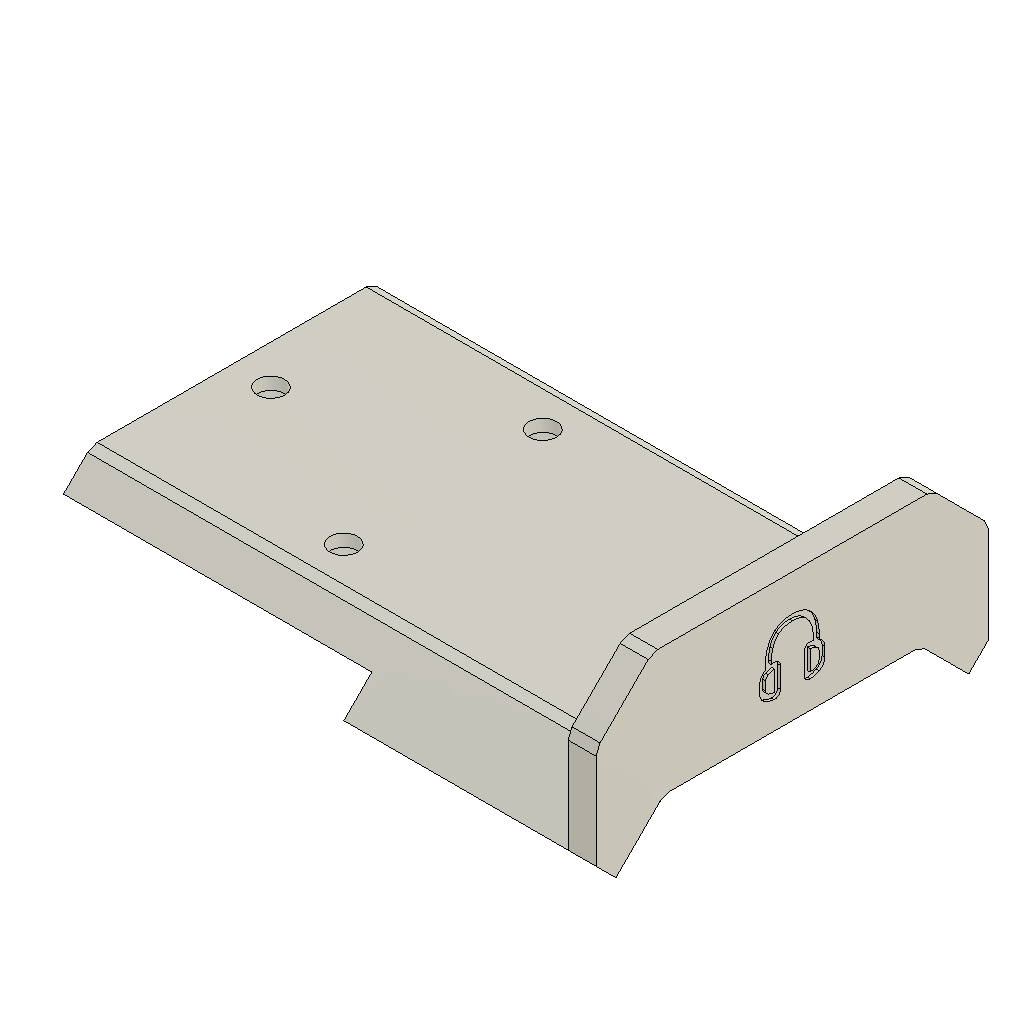
desk (Autodesk Fusion 360 archive; units mm, degrees)
design "headphone holder"
Autodesk Fusion 360 part; units mm, degrees
sketch "Sketch1" plane through (0, 0, 0) normal (1, 0, 0) x (0, 1, 0)
  line L0 (-35, 0) -> (35, 0)
  line L1 (-35, 0) -> (-25, 10)
  line L2 (-25, 10) -> (25, 10)
  line L3 (25, 10) -> (35, 0)
  line L4 (-31.4645, -3.5355) -> (-22.9289, 5)
  line L5 (-22.9289, 5) -> (22.9289, 5)
  line L6 (22.9289, 5) -> (31.4645, -3.5355)
  line L7 (31.4645, -3.5355) -> (35, 0)
  line L8 (-31.4645, -3.5355) -> (-35, 0)
  dimension "d1" = 70
  dimension "d2" = 5
  constraint horizontal L0
  constraint parallel L0 L2
  constraint perpendicular L3 L7
  constraint perpendicular L1 L8
  measures "d1" distance of L0.start L0.end
extrude "Extrude1" add sketch "Sketch1" against normal blind 40 contours L0 L1 L2 L3 L4 L5 L6 | L0 L4 L8 | L0 L6 L7 makes body 1
chamfer "Chamfer1" distance 1 angle 45 4 edges at (-20, 25, 10) (-20, -25, 10) (-20, 22.9289, 5) (-20, -22.9289, 5) tangent chain off on bodies 1
sketch "Sketch2" plane through (0, 0, 0) normal (0, 0, 1) x (1, 0, 0)
  line L0 (0, -35) -> (5, -35)
  line L1 (5, -35) -> (5, 35)
  line L2 (5, 35) -> (0, 35)
  line L3 (0, 35) -> (0, -35)
  constraint horizontal L0
  constraint vertical L1
  constraint horizontal L2
  constraint vertical L3
extrude "Extrude2" add sketch "Sketch2" along normal blind 28 and the other way blind 6 bodies 1
extrude "Extrude3" cut 1 faces at (0, 7.3096, -0.6904) along direction (1, 0, 0) blind 37 on bodies 1 bodies 1
sketch "Sketch3" plane through (0, 0, 0) normal (-1, 0, 0) x (0, -1, 0)
  line L0 (-35, 0) -> (-25.7071, 9.2929)
  line L1 (-25.7071, 9.2929) -> (-24, 10)
  line L2 (-24, 10) -> (24, 10)
  line L3 (24, 10) -> (25.7071, 9.2929)
  line L4 (25.7071, 9.2929) -> (35, 0)
  line L5 (35, 0) -> (35, 28)
  line L6 (35, 28) -> (-35, 28)
  line L7 (-35, 28) -> (-35, 0)
  line L8 (-22.9289, 23) -> (22.9289, 23)
  line L9 (22.9289, 23) -> (31.4645, 14.4645)
  line L10 (-31.4645, 14.4645) -> (-22.9289, 23)
  line L11 (25, 28) -> (35, 18)
  line L12 (31.4645, 14.4645) -> (35, 18)
  line L13 (-31.4645, 14.4645) -> (-35, 18)
  line L14 (-35, 18) -> (-25, 28)
  line L15 (-35, 18) -> (35, 18)
  line L16 (-25, 28) -> (25, 28)
  point P0 (0, 18)
  dimension "d12" = 5
  dimension "d13" = 70
  constraint horizontal L15
  constraint parallel L15 L16
  constraint perpendicular L11 L12
  constraint perpendicular L13 L14
  measures "d13" distance of L11.end L13.end
extrude "Extrude4" cut sketch "Sketch3" against normal blind 10 contours L6 L7 L14 | L5 L6 L11 bodies 1
chamfer "Chamfer2" distance 1 angle 45 4 edges at (2.5, -25, 28) (2.5, 25, 28) (2.5, -35, 18) (2.5, 35, 18) tangent chain off on bodies 1
sketch "Sketch4" plane through (0, 0, 10) normal (0, 0, 1) x (-1, 0, 0)
  line L0 (40, 24) -> (0, 24)
  line L1 (0, 24) -> (0, -24)
  line L2 (0, -24) -> (40, -24)
  line L3 (40, -24) -> (40, 24)
  line L4 (40, 35) -> (95, 35)
  line L5 (95, 35) -> (95, -35)
  line L6 (95, -35) -> (40, -35)
  line L7 (40, -35) -> (40, 35)
  constraint horizontal L4
  constraint vertical L5
  constraint horizontal L6
  constraint vertical L7
extrude "Extrude5" add sketch "Sketch4" against normal blind 4 contours L3 L4 L5 L6 L7 bodies 1
extrude "Extrude6" cut 2 faces at (-40, -29.9024, 8.431) (-40, 29.9024, 8.431) along direction (-1, 0, 0) blind 90 on bodies 1 bodies 1
move_face "OffsetFaces1" offset 1 1 faces at (-76.6667, 8, 6) on bodies 1
sketch "Sketch5" plane through (0, 0, 10) normal (0, 0, 1) x (-1, 0, 0)
  line L0 (95, 24) -> (0, 24)
  line L1 (0, 24) -> (0, -24)
  line L2 (0, -24) -> (95, -24)
  line L3 (95, -24) -> (95, 24)
  circle A0 centre (88, 0) radius 2.45
  line L4 (95, -29.3) -> (40, -29.3)
  line L5 (40, -29.3) -> (40, 29.3)
  line L6 (40, 29.3) -> (95, 29.3)
  line L7 (95, 29.3) -> (95, -29.3)
  circle A1 centre (57.25, 17.7535) radius 2.45
  circle A2 centre (57.25, -17.7535) radius 2.45
  circle A3 centre (67.5, 0) radius 1.5
  point P0 (67.5, 0)
  dimension "d23" = 4.9
  dimension "d25" = 360
  constraint horizontal L4
  constraint vertical L5
  constraint horizontal L6
  constraint vertical L7
  constraint coincident P0 A3.centre
  measures "d23" diameter of A0
extrude "Extrude7" cut sketch "Sketch5" against normal blind 8 contours A0 | A1 | A2 bodies 1
sketch "Sketch6" plane through (0, 0, 5) normal (0, 0, -1) x (1, 0, 0)
  circle A0 centre (-88, 0) radius 2.45
  circle A1 centre (-57.25, 17.7535) radius 2.45
  circle A2 centre (-57.25, -17.7535) radius 2.45
  line L0 (-95, 30) -> (-95, -30)
  line L1 (-40, 21.9289) -> (-40, 30)
  line L2 (-40, -21.9289) -> (5, -21.9289)
  line L3 (5, -21.9289) -> (5, 21.9289)
  line L4 (5, 21.9289) -> (-40, 21.9289)
  circle A3 centre (-57.25, -17.7535) radius 4.5
  circle A4 centre (-88, 0) radius 4.5
  circle A5 centre (-57.25, 17.7535) radius 4.5
  circle A6 centre (-57.25, -17.7535) radius 2.45
  circle A7 centre (-88, 0) radius 2.45
  circle A8 centre (-57.25, 17.7535) radius 2.45
  circle A9 through (-54.8, -17.7535, -2.8) (-58.475, -15.6318, -2.8) (-58.475, -19.8753, -2.8)
  circle A10 through (-85.55, 0, -2.8) (-89.225, 2.1218, -2.8) (-89.225, -2.1218, -2.8)
  circle A11 through (-54.8, 17.7535, -2.8) (-58.475, 19.8753, -2.8) (-58.475, 15.6318, -2.8)
  line L5 (-40, 30) -> (-95, 30)
  line L6 (-95, -30) -> (-40, -30)
  line L7 (-40, -30) -> (-40, -21.9289)
  dimension "d28" = 9
  dimension "d29" = 9
  dimension "d30" = 9
  constraint concentric A2 A3
  constraint concentric A0 A4
  constraint concentric A1 A5
  constraint concentric A3 A6
  constraint concentric A4 A7
  constraint concentric A5 A8
  measures "d28" diameter of A3
  measures "d29" diameter of A4
  measures "d30" diameter of A5
loft "Loft1" add profiles "Sketch6", "Sketch6" section 1 contours A2 A6 | A3 section 2 contours A9 in plane through (0, 0, 7.8) normal (0, 0, -1) separate body makes body 2
extrude "Extrude8" add sketch "Sketch5" along normal blind 2 separate body contours A3 makes body 3
pattern_circular "C-Pattern1" count 3 over 360 about axis through (-67.5, 0, 12) along (0, 0, 1) of bodies 2 makes body 4 at (-87.1, -3.943, 5.6222) makes body 5 at (-53.2507, -17.1507, 5.6222)
delete_body "RemoveBody1" bodies 3
combine "Combine1" operation cut target body 1 tool bodies 5 2 4
sketch "Sketch8" plane through (5, 0, 0) normal (1, 0, 0) x (0, 1, 0)
  line L0 (35, 17) -> (34.2929, 18.7071)
  line L1 (34.2929, 18.7071) -> (25.7071, 27.2929)
  line L2 (25.7071, 27.2929) -> (24, 28)
  line L3 (24, 28) -> (-24, 28)
  line L4 (-24, 28) -> (-25.7071, 27.2929)
  line L5 (-25.7071, 27.2929) -> (-34.2929, 18.7071)
  line L6 (-34.2929, 18.7071) -> (-35, 17)
  line L7 (-35, 17) -> (-35, 0)
  line L8 (-35, 0) -> (-31.4645, -3.5355)
  line L9 (-31.4645, -3.5355) -> (-23.636, 4.2929)
  line L10 (-23.636, 4.2929) -> (-21.9289, 5)
  line L11 (-21.9289, 5) -> (21.9289, 5)
  line L12 (21.9289, 5) -> (23.636, 4.2929)
  line L13 (23.636, 4.2929) -> (31.4645, -3.5355)
  line L14 (31.4645, -3.5355) -> (35, 0)
  line L15 (35, 0) -> (35, 17)
  spline S0 degree 3 poles (-4.7708, 15.1652) (-4.7753, 15.2093) (-4.7804, 15.2652) (-4.7853, 15.3315) knots 0 0 0 0 1 1 1 1
  spline S1 degree 3 poles (-4.7853, 15.3315) (-4.7981, 15.5028) (-4.8102, 15.7448) (-4.808, 16.0343) knots 0 0 0 0 1 1 1 1
  spline S2 degree 3 poles (-4.808, 16.0343) (-4.8036, 16.6098) (-4.7429, 17.3905) (-4.5093, 18.1812) knots 0 0 0 0 1 1 1 1
  spline S3 degree 3 poles (-4.5093, 18.1812) (-4.2757, 18.972) (-3.8605, 19.8008) (-3.1279, 20.4328) knots 0 0 0 0 1 1 1 1
  spline S4 degree 3 poles (-3.1279, 20.4328) (-2.3869, 21.0721) (-1.3663, 21.4708) (0, 21.4708) knots 0 0 0 0 1 1 1 1
  spline S5 degree 3 poles (0, 21.4708) (1.3663, 21.4708) (2.3869, 21.0721) (3.1279, 20.4328) knots 0 0 0 0 1 1 1 1
  spline S6 degree 3 poles (3.1279, 20.4328) (3.8605, 19.8008) (4.2757, 18.972) (4.5093, 18.1812) knots 0 0 0 0 1 1 1 1
  spline S7 degree 3 poles (4.5093, 18.1812) (4.7429, 17.3905) (4.8036, 16.6098) (4.808, 16.0343) knots 0 0 0 0 1 1 1 1
  spline S8 degree 3 poles (4.808, 16.0343) (4.8102, 15.7448) (4.7981, 15.5028) (4.7853, 15.3315) knots 0 0 0 0 1 1 1 1
  spline S9 degree 3 poles (4.7853, 15.3315) (4.7804, 15.2652) (4.7753, 15.2093) (4.7709, 15.1652) knots 0 0 0 0 1 1 1 1
  line L16 (4.7709, 15.1652) -> (4.7735, 15.1637)
  spline S10 degree 3 poles (4.7735, 15.1637) (5.3087, 14.8742) (5.8208, 14.3615) (5.8208, 13.5333) knots 0 0 0 0 1 1 1 1
  line L17 (5.8208, 13.5333) -> (5.8208, 11.9458)
  spline S11 degree 3 poles (5.8208, 11.9458) (5.8208, 11.1177) (5.3087, 10.6049) (4.7735, 10.3154) knots 0 0 0 0 1 1 1 1
  spline S12 degree 3 poles (4.7735, 10.3154) (4.2531, 10.0339) (3.6452, 9.9196) (3.2363, 9.8703) knots 0 0 0 0 1 1 1 1
  spline S13 degree 3 poles (3.2363, 9.8703) (2.5951, 9.7931) (2.1167, 10.3153) (2.1167, 10.8875) knots 0 0 0 0 1 1 1 1
  line L18 (2.1167, 10.8875) -> (2.1167, 14.5917)
  spline S14 degree 3 poles (2.1167, 14.5917) (2.1167, 15.1639) (2.5951, 15.6861) (3.2363, 15.6089) knots 0 0 0 0 1 1 1 1
  spline S15 degree 3 poles (3.2363, 15.6089) (3.3823, 15.5913) (3.5538, 15.5654) (3.7376, 15.5265) knots 0 0 0 0 1 1 1 1
  spline S16 degree 3 poles (3.7376, 15.5265) (3.7453, 15.6614) (3.7512, 15.8312) (3.7497, 16.0263) knots 0 0 0 0 1 1 1 1
  spline S17 degree 3 poles (3.7497, 16.0263) (3.7458, 16.5423) (3.6907, 17.2168) (3.4944, 17.8813) knots 0 0 0 0 1 1 1 1
  spline S18 degree 3 poles (3.4944, 17.8813) (3.298, 18.5457) (2.9691, 19.1721) (2.4366, 19.6315) knots 0 0 0 0 1 1 1 1
  spline S19 degree 3 poles (2.4366, 19.6315) (1.9126, 20.0836) (1.1472, 20.4125) (0, 20.4125) knots 0 0 0 0 1 1 1 1
  spline S20 degree 3 poles (0, 20.4125) (-1.1472, 20.4125) (-1.9125, 20.0836) (-2.4366, 19.6315) knots 0 0 0 0 1 1 1 1
  spline S21 degree 3 poles (-2.4366, 19.6315) (-2.9691, 19.1721) (-3.298, 18.5457) (-3.4943, 17.8813) knots 0 0 0 0 1 1 1 1
  spline S22 degree 3 poles (-3.4943, 17.8813) (-3.6907, 17.2168) (-3.7457, 16.5423) (-3.7497, 16.0263) knots 0 0 0 0 1 1 1 1
  spline S23 degree 3 poles (-3.7497, 16.0263) (-3.7511, 15.8312) (-3.7453, 15.6614) (-3.7376, 15.5265) knots 0 0 0 0 1 1 1 1
  spline S24 degree 3 poles (-3.7376, 15.5265) (-3.5538, 15.5654) (-3.3823, 15.5913) (-3.2363, 15.6089) knots 0 0 0 0 1 1 1 1
  spline S25 degree 3 poles (-3.2363, 15.6089) (-2.5951, 15.6861) (-2.1167, 15.1639) (-2.1167, 14.5917) knots 0 0 0 0 1 1 1 1
  line L19 (-2.1167, 14.5917) -> (-2.1167, 10.8875)
  spline S26 degree 3 poles (-2.1167, 10.8875) (-2.1167, 10.3153) (-2.5951, 9.7931) (-3.2363, 9.8703) knots 0 0 0 0 1 1 1 1
  spline S27 degree 3 poles (-3.2363, 9.8703) (-3.6452, 9.9196) (-4.2531, 10.0339) (-4.7735, 10.3154) knots 0 0 0 0 1 1 1 1
  spline S28 degree 3 poles (-4.7735, 10.3154) (-5.3086, 10.6049) (-5.8208, 11.1177) (-5.8208, 11.9458) knots 0 0 0 0 1 1 1 1
  line L20 (-5.8208, 11.9458) -> (-5.8208, 13.5333)
  spline S29 degree 3 poles (-5.8208, 13.5333) (-5.8208, 14.3615) (-5.3086, 14.8742) (-4.7735, 15.1637) knots 0 0 0 0 1 1 1 1
  line L21 (-4.7735, 15.1637) -> (-4.7708, 15.1652)
  spline S30 degree 3 poles (3.175, 10.9294) (3.5256, 10.9762) (3.9445, 11.0703) (4.27, 11.2463) knots 0 0 0 0 1 1 1 1
  spline S31 degree 3 poles (4.27, 11.2463) (4.6013, 11.4255) (4.7625, 11.6414) (4.7625, 11.9458) knots 0 0 0 0 1 1 1 1
  line L22 (4.7625, 11.9458) -> (4.7625, 13.5333)
  spline S32 degree 3 poles (4.7625, 13.5333) (4.7625, 13.8378) (4.6013, 14.0537) (4.27, 14.2328) knots 0 0 0 0 1 1 1 1
  spline S33 degree 3 poles (4.27, 14.2328) (3.9445, 14.4089) (3.5256, 14.5029) (3.175, 14.5498) knots 0 0 0 0 1 1 1 1
  line L23 (3.175, 14.5498) -> (3.175, 10.9294)
  spline S34 degree 3 poles (-3.175, 14.5498) (-3.5256, 14.5029) (-3.9445, 14.4089) (-4.27, 14.2328) knots 0 0 0 0 1 1 1 1
  spline S35 degree 3 poles (-4.27, 14.2328) (-4.6012, 14.0537) (-4.7625, 13.8378) (-4.7625, 13.5333) knots 0 0 0 0 1 1 1 1
  line L24 (-4.7625, 13.5333) -> (-4.7625, 11.9458)
  spline S36 degree 3 poles (-4.7625, 11.9458) (-4.7625, 11.6414) (-4.6012, 11.4255) (-4.27, 11.2463) knots 0 0 0 0 1 1 1 1
  spline S37 degree 3 poles (-4.27, 11.2463) (-3.9445, 11.0703) (-3.5256, 10.9762) (-3.175, 10.9294) knots 0 0 0 0 1 1 1 1
  line L25 (-3.175, 10.9294) -> (-3.175, 14.5498)
extrude "Extrude9" cut sketch "Sketch8" against normal blind 0.5 contours S0 S1 S2 S3 S4 S5 S6 S7 S8 S9 L16 S10 L17 S11 S12 S13 L18 S14 S15 S16 S17 S18 S19 S20 S21 S22 S23 S24 S25 L19 S26 S27 S28 L20 S29 L21 bodies 1
